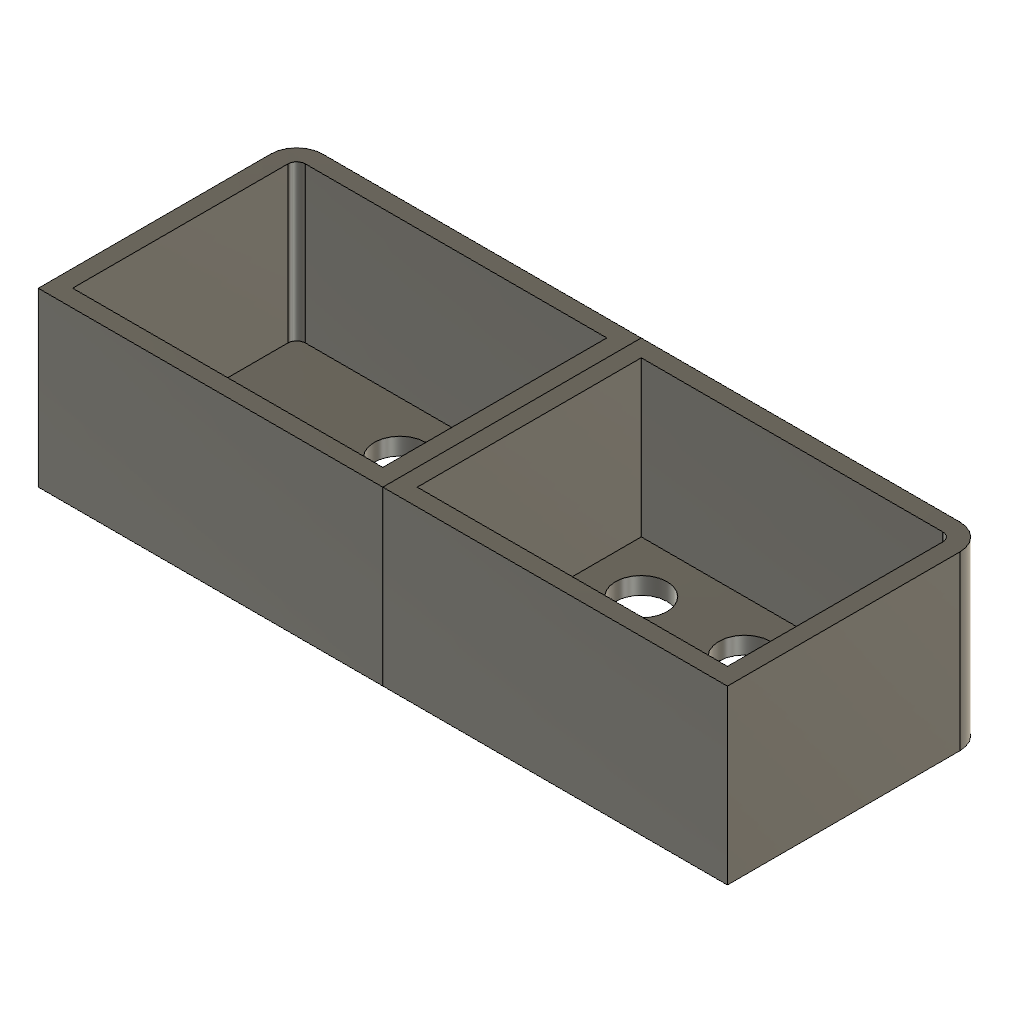
MultiFeature (Autodesk Fusion 360 design; units mm, degrees)
part number: 2026-11-12-11-46-42-881
Autodesk Fusion 360 part; units mm, degrees
sketch "Base sketch" plane through (0, 0, 0) normal (0, 0, 1) x (1, 0, 0)
  line L0 (0, 0) -> (40, 0)
  line L1 (40, 0) -> (40, 30)
  line L2 (40, 30) -> (0, 30)
  line L3 (0, 30) -> (0, 0)
extrude "Base extrude" add sketch "Base sketch" along normal blind 20 makes body 1
fillet "Corner fillet" radius 3 1 edges at (40, 30, 10) on bodies 1
shell "Open shell" thickness 2 removed faces 1 at (25.6667, 10, 20) on bodies 1
sketch "Pocket sketch" plane through (0, 0, 0) normal (0, 0, 1) x (1, 0, 0)
  circle A0 centre (8, 8) radius 3
extrude "Pocket extrude" cut sketch "Pocket sketch" along normal blind 20 bodies 1
pattern_linear "Pocket grid" count 2 spacing 12 along (1, 0, 0) count 2 spacing 14 along (0, 1, 0) of "Pocket extrude"
mirror "Part mirror" about plane through (0, 0, 0) normal (1, 0, 0) of bodies 1 makes body 2
